Autodesk Fusion 360 part; units mm, degrees
(part 4 of 4)
sketch "草图7 (20)" plane through (0, 0, 210) normal (0, 0, 1) x (1, 0, 0) in component "10_CPU_140_FAN_MOUNT"
  line L0 (170.4, -19) -> (182.4, -19)
  line L1 (182.4, -19) -> (182.4, -9)
  line L2 (182.4, -9) -> (170.4, -9)
  line L3 (170.4, -9) -> (170.4, -19)
extrude "Integral 3 mm fan panel fastening tab'" add sketch "草图7 (20)" along normal blind 3 bodies 2 in component "10_CPU_140_FAN_MOUNT"
ref_plane "工作平面8" through (0, 0, 210) normal (0, 0, 1) x (1, 0, 0) in component "10_CPU_140_FAN_MOUNT"
sketch "草图8 (20)" plane through (0, 0, 210) normal (0, 0, 1) x (1, 0, 0) in component "10_CPU_140_FAN_MOUNT"
  circle A0 centre (176.4, -14) radius 1.7
extrude "M3x6 fan panel tab clearance'" cut sketch "草图8 (20)" along normal blind 3.01 bodies 2 in component "10_CPU_140_FAN_MOUNT"
ref_plane "工作平面18" through (0, 0, 148) normal (0, 0, 1) x (1, 0, 0) in component "20_ONE_PIECE_DUAL_140_FAN_RAIL_284mm"
sketch "草图18 (3)" plane through (0, 0, 148) normal (0, 0, 1) x (1, 0, 0) in component "20_ONE_PIECE_DUAL_140_FAN_RAIL_284mm"
  line L0 (170.4, -19) -> (182.4, -19)
  line L1 (182.4, -19) -> (182.4, -9)
  line L2 (182.4, -9) -> (170.4, -9)
  line L3 (170.4, -9) -> (170.4, -19)
extrude "Integral fan panel tab support pad (2)" add sketch "草图18 (3)" along normal blind 12 bodies 35 in component "20_ONE_PIECE_DUAL_140_FAN_RAIL_284mm"
ref_plane "工作平面19" through (0, 0, 153.5) normal (0, 0, 1) x (1, 0, 0) in component "20_ONE_PIECE_DUAL_140_FAN_RAIL_284mm"
sketch "草图19 (3)" plane through (0, 0, 153.5) normal (0, 0, 1) x (1, 0, 0) in component "20_ONE_PIECE_DUAL_140_FAN_RAIL_284mm"
  circle A0 centre (176.4, -14) radius 2.35
extrude "H4.5 insert for fan panel M3x6 fastening (2)" cut sketch "草图19 (3)" along normal blind 6.51 bodies 35 in component "20_ONE_PIECE_DUAL_140_FAN_RAIL_284mm"
ref_plane "工作平面9" through (0, 0, 210) normal (0, 0, 1) x (1, 0, 0) in component "10_CPU_140_FAN_MOUNT"
sketch "草图9 (20)" plane through (0, 0, 210) normal (0, 0, 1) x (1, 0, 0) in component "10_CPU_140_FAN_MOUNT"
  line L0 (270.4, -19) -> (282.4, -19)
  line L1 (282.4, -19) -> (282.4, -9)
  line L2 (282.4, -9) -> (270.4, -9)
  line L3 (270.4, -9) -> (270.4, -19)
extrude "Integral 3 mm fan panel fastening tab (1)'" add sketch "草图9 (20)" along normal blind 3 bodies 2 in component "10_CPU_140_FAN_MOUNT"
ref_plane "工作平面10" through (0, 0, 210) normal (0, 0, 1) x (1, 0, 0) in component "10_CPU_140_FAN_MOUNT"
sketch "草图10 (17)" plane through (0, 0, 210) normal (0, 0, 1) x (1, 0, 0) in component "10_CPU_140_FAN_MOUNT"
  circle A0 centre (276.4, -14) radius 1.7
extrude "M3x6 fan panel tab clearance (1)'" cut sketch "草图10 (17)" along normal blind 3.01 bodies 2 in component "10_CPU_140_FAN_MOUNT"
ref_plane "工作平面20" through (0, 0, 148) normal (0, 0, 1) x (1, 0, 0) in component "20_ONE_PIECE_DUAL_140_FAN_RAIL_284mm"
sketch "草图20 (3)" plane through (0, 0, 148) normal (0, 0, 1) x (1, 0, 0) in component "20_ONE_PIECE_DUAL_140_FAN_RAIL_284mm"
  line L0 (270.4, -19) -> (282.4, -19)
  line L1 (282.4, -19) -> (282.4, -9)
  line L2 (282.4, -9) -> (270.4, -9)
  line L3 (270.4, -9) -> (270.4, -19)
extrude "Integral fan panel tab support pad (3)" add sketch "草图20 (3)" along normal blind 12 bodies 35 in component "20_ONE_PIECE_DUAL_140_FAN_RAIL_284mm"
ref_plane "工作平面21" through (0, 0, 153.5) normal (0, 0, 1) x (1, 0, 0) in component "20_ONE_PIECE_DUAL_140_FAN_RAIL_284mm"
sketch "草图21 (3)" plane through (0, 0, 153.5) normal (0, 0, 1) x (1, 0, 0) in component "20_ONE_PIECE_DUAL_140_FAN_RAIL_284mm"
  circle A0 centre (276.4, -14) radius 2.35
extrude "H4.5 insert for fan panel M3x6 fastening (3)" cut sketch "草图21 (3)" along normal blind 6.51 bodies 35 in component "20_ONE_PIECE_DUAL_140_FAN_RAIL_284mm"
component "10_GPU_140_FAN_MOUNT" placed x (1, 0, 0) y (0, 1, 0) z (0, 0, 1) at (0, 0, -50)
component "10_CPU_140_FAN_MOUNT" placed x (1, 0, 0) y (0, 1, 0) z (0, 0, 1) at (0, 0, -50)
component "REF_CASE_FAN_GPU_140x140x25" placed x (1, 0, 0) y (0, 1, 0) z (0, 0, 1) at (0, 0, -50)
component "REF_AIRFLOW_GPU_FRONT_TO_REAR" placed x (1, 0, 0) y (0, 1, 0) z (0, 0, 1) at (0, 0, -50)
component "REF_CASE_FAN_CPU_140x140x25" placed x (1, 0, 0) y (0, 1, 0) z (0, 0, 1) at (0, 0, -50)
component "REF_AIRFLOW_CPU_FRONT_TO_REAR" placed x (1, 0, 0) y (0, 1, 0) z (0, 0, 1) at (0, 0, -50)
component "REF_BOARD_304.8x243.84_NUMBERED_HOLES" placed x (1, 0, 0) y (0, 1, 0) z (0, 0, 1) at (0, 0, -50)
component "REF_CPU_RIGHT" placed x (1, 0, 0) y (0, 1, 0) z (0, 0, 1) at (0, 0, -50)
component "REF_MEMORY_RIGHT_FRONT" placed x (1, 0, 0) y (0, 1, 0) z (0, 0, 1) at (0, 0, -50)
component "REF_PRIMARY_PCIE_X126.4_APPROX" placed x (1, 0, 0) y (0, 1, 0) z (0, 0, 1) at (0, 0, -50)
component "REF_SECOND_LONG_PCIE_X60_APPROX" placed x (1, 0, 0) y (0, 1, 0) z (0, 0, 1) at (0, 0, -50)
component "REF_GPU_FANS_TO_MINUS_X" placed x (1, 0, 0) y (0, 1, 0) z (0, 0, 1) at (0, 0, -50)
component "REF_GPU_FAN_MARKERS_MINUS_X" placed x (1, 0, 0) y (0, 1, 0) z (0, 0, 1) at (0, 0, -50)
component "04_front_GROUND_BAR_290mm_FLAT_PSU" placed x (1, 0, 0) y (0, 1, 0) z (0, 0, 1) at (0, 0, 0)
component "04_rear_GROUND_BAR_290mm_FLAT_PSU" placed x (1, 0, 0) y (0, 1, 0) z (0, 0, 1) at (0, 0, 0)
component "05_CENTERED_FLAT_PSU_CRADLE_OPEN_INTAKE" placed x (1, 0, 0) y (0, 1, 0) z (0, 0, 1) at (0, 0, 0)
component "REF_PSU_FLAT_CENTERED_150x140x86" placed x (1, 0, 0) y (0, 1, 0) z (0, 0, 1) at (0, 0, 0)
component "REF_PSU_INTAKE_DOWN_MINUS_Z" placed x (1, 0, 0) y (0, 1, 0) z (0, 0, 1) at (0, 0, 0)
component "REF_PSU_REAR_EXHAUST_PLUS_Y" placed x (1, 0, 0) y (0, 1, 0) z (0, 0, 1) at (0, 0, 0)
component "12_front_PCI_SUPPORT_FRAME" placed x (1, 0, 0) y (0, 1, 0) z (0, 0, 1) at (0, 0, 0)
component "12_front_CPU_SUPPORT_FRAME" placed x (1, 0, 0) y (0, 1, 0) z (0, 0, 1) at (0, 0, 0)
component "07_GPU_REINFORCED_REAR_TOWER" placed x (1, 0, 0) y (0, 1, 0) z (0, 0, 1) at (0, 0, 0)
component "08_GPU_UPPER_EAR_LEDGE_ADJUSTABLE" placed x (1, 0, 0) y (0, 1, 0) z (0, 0, 1) at (0, 0, 0)
component "08_GPU_LOWER_TWO_TAB_RECEIVER_ADJUSTABLE" placed x (1, 0, 0) y (0, 1, 0) z (0, 0, 1) at (0, 0, 0)
component "16_CPU_VERTICAL_SIDE_FLUSH_TO_BEAM" placed x (1, 0, 0) y (0, 1, 0) z (0, 0, 1) at (0, 0, 0)
component "16_PCI_INSET_SIDE_16_45mm" placed x (1, 0, 0) y (0, 1, 0) z (0, 0, 1) at (0, 0, 0)
component "19_PCI_LONGITUDINAL_BOARD_RAIL_243_84mm" placed x (1, 0, 0) y (0, 1, 0) z (0, 0, 1) at (0, 0, 0)
component "19_MID_LONGITUDINAL_BOARD_RAIL_243_84mm" placed x (1, 0, 0) y (0, 1, 0) z (0, 0, 1) at (0, 0, 0)
component "19_CPU_LONGITUDINAL_BOARD_RAIL_243_84mm" placed x (1, 0, 0) y (0, 1, 0) z (0, 0, 1) at (0, 0, 0)
component "18_ONE_PIECE_REAR_LOAD_BEAM_304_45mm" placed x (1, 0, 0) y (0, 1, 0) z (0, 0, 1) at (0, 0, 0)
component "20_ONE_PIECE_DUAL_140_FAN_RAIL_284mm" placed x (1, 0, 0) y (0, 1, 0) z (0, 0, 1) at (0, 0, 0)
equation "desk_limit = 290 mm" comment "V03 layout review; fixed profiles require regeneration"
equation "footprint_width = 290 mm" comment "V03 layout review; fixed profiles require regeneration"
equation "board_width = 304.8 mm" comment "V03 layout review; fixed profiles require regeneration"
equation "board_depth = 243.84 mm" comment "V03 layout review; fixed profiles require regeneration"
equation "board_bottom_height = 208 mm" comment "V03 layout review; fixed profiles require regeneration"
equation "approx_slot_x = 126.4 mm" comment "V03 layout review; fixed profiles require regeneration"
equation "v13_rear_overall_length = 304.45 mm" comment "V13 manufacturing reference; geometry controlled by named feature sketches"
equation "v13_fan_rail_length = 284 mm" comment "V13 manufacturing reference; geometry controlled by named feature sketches"
equation "v13_bed_side = 256 mm" comment "V13 manufacturing reference; geometry controlled by named feature sketches"
equation "v13_insert_pilot = 4.7 mm" comment "V13 manufacturing reference; geometry controlled by named feature sketches"
equation "v13_screw_clearance = 3.4 mm" comment "V13 manufacturing reference; geometry controlled by named feature sketches"
equation "v13_head_well = 6.6 mm" comment "V13 manufacturing reference; geometry controlled by named feature sketches"
